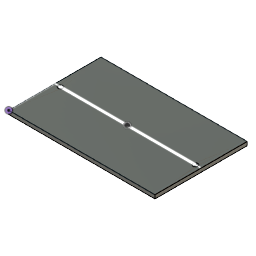
Battery mount top cover (Autodesk Fusion 360 design; units mm, degrees)
Autodesk Fusion 360 part; units mm, degrees
sketch "Sketch1" plane through (0, 0, 0) normal (0, 0, 1) x (1, 0, 0)
  line L0 (0, 0) -> (102, 0)
  line L1 (102, 0) -> (102, 65)
  line L2 (102, 65) -> (0, 65)
  line L3 (0, 65) -> (0, 0)
  dimension "d1" = 102
  dimension "d2" = 65
  constraint horizontal L0
  constraint vertical L1
  constraint horizontal L2
  constraint vertical L3
  constraint coincident L0.start L3.end
  measures "d1" distance of L0.start L0.end
  measures "d2" distance of L0.start L2.end
extrude "Extrude1" add sketch "Sketch1" along normal blind 2.6
sketch "Sketch2" plane through (0, 0, 2.6) normal (0, 0, 1) x (-1, 0, 0)
  line L0 (0, -65) -> (0, 0)
  line L1 (0, 0) -> (-102, 0)
  line L2 (-102, 0) -> (-102, -65)
  line L3 (-102, -65) -> (0, -65)
  line L4 (0, 0) -> (0, -32.5)
  line L5 (0, -32.5) -> (-102, -32.5)
  line L6 (-98, -32) -> (-4, -32)
  line L7 (-4, -32) -> (-4, -33)
  line L8 (-4, -33) -> (-98, -33)
  line L9 (-98, -33) -> (-98, -32)
  line L10 (-98, -32) -> (-4, -33) construction
  line L11 (-4, -32) -> (-98, -33) construction
  point P0 (-51, -32.5)
  dimension "d5" = 94
  dimension "d6" = 1
  constraint coincident L0.end L1.start
  constraint midpoint L0 L4.end
  constraint midpoint L2 L5.end
  constraint horizontal L6
  constraint perpendicular L6 L7
  constraint parallel L6 L8
  constraint parallel L7 L9
  constraint coincident L10 P0
  constraint coincident L11 P0
  constraint midpoint L5 P0
  measures "d5" distance of L7.end L8.end
  measures "d6" distance of L6.end L7.end
sketch "Sketch3" plane through (0, 0, 2.6) normal (0, 0, 1) x (-1, 0, 0)
  circle A0 centre (-98, -32.5) radius 1.7
  circle A1 centre (-4, -32.5) radius 1.7
  dimension "d7" = 3.4
  dimension "d8" = 3.4
  measures "d7" diameter of A0
  measures "d8" diameter of A1
extrude "Extrude2" cut sketch "Sketch3" against normal blind 9.5
extrude "Extrude3" add 1 faces at (102, 21.6667, 0.8667) along direction (1, 0, 0) blind 1
sketch "Sketch4" plane through (0, 0, 2.6) normal (0, 0, 1) x (-1, 0, 0)
  circle A0 centre (-98, -32.5) radius 1.7
  line L0 (-98, -32.5) -> (-99, -32.5)
  dimension "d13" = 3.4
  dimension "d14" = 1
  constraint coincident A0.centre L0.start
  constraint horizontal L0
  measures "d13" diameter of A0
  measures "d14" distance of A0.centre L0.end
sketch "Sketch5" plane through (0, 0, 0) normal (0, 0, -1) x (1, 0, 0)
  circle A0 centre (4, -32.5) radius 1.7
  circle A1 centre (98, -32.5) radius 1.7
  line L0 (0, 0) -> (0, -65)
  line L1 (0, -65) -> (103, -65)
  line L2 (103, -65) -> (103, 0)
  line L3 (103, 0) -> (0, 0)
  circle A2 centre (99, -32.5) radius 1.7
  dimension "d15" = 3.4
  measures "d15" diameter of A2
extrude "Extrude4" add sketch "Sketch4" against normal blind 2.6
extrude "Extrude5" cut sketch "Sketch5" against normal blind 2.6 contours A1 A2 | A1 A2 picked at (98.1032, -32.5) picked at (100.3608, -32.4188)
